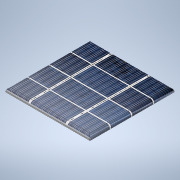
# Autodesk Inventor part: 太阳能发电板
Saved by Autodesk Inventor 2021.4 (Build 254397000, 397)
## iProperties
Created: 2024-04-28
Part Number: 太阳能发电板
Material: 常规
Document SubType Name: Modeling
Designer: PC
Density: 1 g/cm^3
Appearance: 默认
Author: PC
Autodesk Inventor part; units mm, degrees
ref_plane "YZ Plane" through (0, 0, 0) normal (1, 0, 0) x (0, 1, 0)
ref_plane "XY Plane" through (0, 0, 0) normal (0, 0, 1) x (1, 0, 0)
sketch "草图1" plane through (0, 0, 0) normal (0, 1, 0) x (-1, 0, 0)
  line L0 (0, 0) -> (44, 0)
  line L1 (44, 0) -> (44, -44)
  line L2 (44, -44) -> (0, -44)
  line L3 (0, -44) -> (0, 0)
  dimension "d0" = 44
  dimension "d1" = 44
  constraints: 8 end point, 2 parallel, 1 horizontal, 1 perpendicular
  measures "d0" distance of L0.end L1.end
  measures "d1" distance of L1.end L2.end
extrude "拉伸1" add sketch "草图1" along normal blind 2
fillet "圆角1" radius 1.5 4 edges at (-22, 2, 0) (0, 2, -22) (-22, 2, -44) (-44, 2, -22)
ref_plane "工作平面1" through (0, 16, 0) normal (0, 1, 0) x (-1, 0, 0)
sketch "草图2" plane through (0, 16, 0) normal (0, 1, 0) x (-1, 0, 0)
  line L0 (-11.2806, -0.055) -> (55.8447, -0.055) construction
  line L1 (55.8447, -0.055) -> (55.8447, -44.051) construction
  line L2 (55.8447, -44.051) -> (-11.2806, -44.051) construction
  line L3 (-11.2806, -44.051) -> (-11.2806, -0.055) construction
  point P0 (0, 0)
  constraints: 2 other
decal "贴图1"
